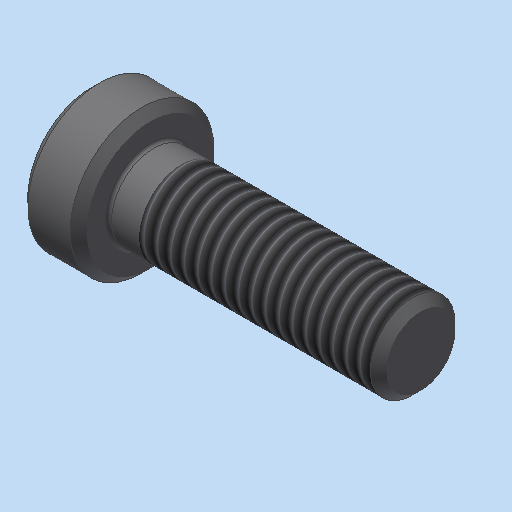
# Autodesk Inventor part: Zylinderschraube_DIN_7984___M5x16
Saved by Autodesk Inventor 2023.3 (Build 273359000, 359)
## iProperties
Shininess: 64.0
Length Units: 11269
Angle Units: 11279
Time Units: 11290
Mass Units: 11283
Length Display Precision: 3
Angle Display Precision: 2
Compacted: True
Part Number: Zylinderschraube_DIN_7984___M5x16
Document SubType Name: Modeling
Created: 2004-04-02
Material: xStahl_AnP_Dummymaterial
Description: =<RBPARTNOTITLE2>
Vendor: NORM8
Designer: S.Riedelsheimer
Manufacturer: Standard
Standards Organization: Custom
Density: 7.85 g/cm^3
Mass: 3.79688 g
Surface Area: 4.63889 cm^2
Volume: 0.48368 cm^3
Appearance: Stahl - normal AnP
DOC_ID: 5 F45 Zylinderschraube_DIN_7984___M5x16
GAIN_REFID: 20__Zylinderschraube_DIN_7984___M5x16:81C07
Control State: 0
Master: False
Checked Out: False
CNS_NB: Zylinderschraube DIN 7984 - M5x16
CNS_NN: DIN 7984
CNS_NT: Zylinderschraube mit Innensechskant und niedrigem Kopf
CNS_NBSYN: Zylinderschraube DIN 7984 - $NENN.
CNS_LINA: Zylinderschraube DIN 7984 - M5x16
CNS_NENN: M5x16
CNS_D: 5.000
CNS_D3: 4.019
CNS_P: 0.800
CNS_L: 16.000
CNS_S: 3.000
CNS_DK: 8.500
CNS_K: 3.500
CNS_LS: 0.500
CNS_LG: 2.400
CNS_R: 0.200
CNS_T: 2.700
CNS_V: 0.500
CNS_KT: X
PSOL_IDENT_0: {C:\partsolutions8\data\23d-libs\bosch_bamberg\schrauben\zylinderschrauben\din_7984.prj},169 {M=Nenn
PSOL_IDENT_1: gewinde},{VTYP=3D},{NB=Zylinderschraube DIN 7984 - M5x16},{NN=DIN 7984},{DATE=4.12.2003},{GEOMDATE=0
PSOL_IDENT_2: 4.12.2003},{VERSION=v1},{LINEID=180},{LINESUBID=-1},{WBVAR=}  {NB=Zylinderschraube DIN 7984 - M5x16}
PSOL_IDENT_3: ,{LINA=Zylinderschraube DIN 7984 - M5x16},{KT=X},{IDNR=},{NENN=M5x16},{D=5.000},{D3=4.019},{P=0.800}
PSOL_IDENT_4: ,{L=16.000},{S=3.000},{DK=8.500},{K=3.500},{LS=0.500},{LG=2.400},{R=0.200},{T=2.700},{V=0.500}
DEF_STKID: T21178
Bezeichnung1: Zylinderschraube DIN 7984 - M5x16
Bezeichnung2: Zylinderschraube mit Innensechskant und
RBDRAWINGMISSINGSPEC: --
AnP_Kategorie: 4
RBPARTNOTITLE1: Hexagon socket head cap screws with low head
RBPARTNOTITLE2: Zylinderschrauben mit Innensechskant mit niedrigem Kopf
RBPARTMADEOF: DIN 7984 - M5x16 - 8.8 - verzinkt
Density: 0.0
Volumn: 0.0
Area: 0.0
PropertySet Name: Model Information
Title: Zylinderschraube DIN 7984 - M5x16
Author: S.Riedelsheimer
Keywords: =<RBPARTMADEOF>
Comments: =<RBSURFACE2>
Revision Number: 01
Autodesk Inventor part; units mm, degrees
sketch "Sketch_1" plane through (0, 0, 0) normal (0, 0, 1) x (1, 0, 0)
  line L0 (16, 0) -> (-3.5, 0)
  line L1 (-3.5, 0) -> (-3.5, 3.75)
  line L2 (-3.5, 3.75) -> (-3, 4.25)
  line L3 (-3, 4.25) -> (-0.5, 4.25)
  line L4 (-0.5, 4.25) -> (0, 3.75)
  line L5 (0, 3.75) -> (0, 2.7)
  arc A0 (0, 2.7) -> (0.2, 2.5) centre (0.2, 2.7) ccw
  line L6 (0.2, 2.5) -> (15.5095, 2.5)
  line L7 (15.5095, 2.5) -> (16, 2.0095)
  line L8 (16, 2.0095) -> (16, 0)
  line L9 (16, 0) -> (-3.5, 0)
  constraints: 20 end point, 2 point on circle, 1 centre point
revolve "Drehung1" add sketch "Sketch_1" angle 360 about axis through (16, 0, 0) along (1, 0, 0)
thread "Gewinde1" size "M5x0.8" class "6g" standard "ANSI Metric M Profile" length 13.6694
sketch "Sketch_2" plane through (-3.5, 0, 0) normal (1, 0, 0) x (0, 0, -1)
  line L0 (-1.5, 0.866) -> (-1.5, -0.866)
  line L1 (-1.5, -0.866) -> (0, -1.7321)
  line L2 (0, -1.7321) -> (1.5, -0.866)
  line L3 (1.5, -0.866) -> (1.5, 0.866)
  line L4 (1.5, 0.866) -> (0, 1.7321)
  line L5 (0, 1.7321) -> (-1.5, 0.866)
  constraints: 12 end point
extrude "Extrusion1" cut sketch "Sketch_2" along normal blind 2.7
ref_plane "IP1_XY" through (0, 0, 0) normal (1, 0, 0) x (0, 0, -1)
ref_plane "IP1_YZ" through (0, 0, 0) normal (0, 0, -1) x (0, 1, 0)
ref_plane "IP2_XY" through (-3.5, 0, 0) normal (1, 0, 0) x (0, 0, -1)
ref_plane "IP2_YZ" through (-3.5, 0, 0) normal (0, 0, -1) x (0, 1, 0)
ref_plane "IP3_XY" through (16, 0, 0) normal (1, 0, 0) x (0, 0, -1)
ref_plane "IP3_YZ" through (16, 0, 0) normal (0, 0, -1) x (0, 1, 0)
